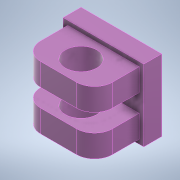
# Autodesk Inventor part: sliding_link
Saved by Autodesk Inventor 2022 (Build 260153000, 153)
## iProperties
Created: 2024-11-08
Part Number: sliding_link
Material: Generic
Document SubType Name: Modeling
Designer: Dell
Density: 1 g/cm^3
Appearance: Smooth - Purple
Author: Dell
Autodesk Inventor part; units mm, degrees
ref_plane "YZ Plane" through (0, 0, 0) normal (1, 0, 0) x (0, 1, 0)
ref_plane "XZ Plane" through (0, 0, 0) normal (0, 1, 0) x (-1, 0, 0)
ref_plane "XY Plane" through (0, 0, 0) normal (0, 0, 1) x (1, 0, 0)
sketch "Sketch1" plane through (0, 0, 0) normal (0, 0, 1) x (1, 0, 0)
  line L0 (0, 0) -> (-9, 0)
  line L1 (-9, 0) -> (-9, 8)
  line L2 (-9, 8) -> (0, 8)
  line L3 (0, 8) -> (0, 0)
  dimension "d0" = 9
  dimension "d1" = 8
  constraints: 8 end point, 2 parallel, 1 horizontal, 1 perpendicular
  measures "d0" distance of L1.end L2.end
  measures "d1" distance of L0.end L1.end
extrude "Extrusion1" add sketch "Sketch1" along normal blind 2
sketch "Sketch2" plane through (0, 0, 2) normal (0, 0, 1) x (1, 0, 0)
  line L0 (0, 0) -> (0, 8) projected
  line L1 (0, 8) -> (-9, 8) projected
  line L2 (-0.5, 0.5) -> (-8.5, 0.5)
  line L3 (-8.5, 0.5) -> (-8.5, 3)
  line L4 (-8.5, 3) -> (-0.5, 3)
  line L5 (-0.5, 3) -> (-0.5, 0.5)
  line L6 (-9, 0) -> (0, 0) projected
  line L7 (-0.5, 5) -> (-8.5, 5)
  line L8 (-8.5, 5) -> (-8.5, 7.5)
  line L9 (-8.5, 7.5) -> (-0.5, 7.5)
  line L10 (-0.5, 7.5) -> (-0.5, 5)
  dimension "d8" = 2.5
  dimension "d9" = 0.5
  dimension "d10" = 2.5
  dimension "d11" = 0.5
  constraints: 16 end point, 4 parallel, 2 horizontal, 2 perpendicular
  measures "d8" distance of L2.end L3.end
  measures "d9" distance between parallel lines of L6 L2
  measures "d10" distance of L7.end L8.end
  measures "d11" distance between parallel lines of L9 L1
extrude "Extrusion2" add sketch "Sketch2" along normal blind 5
sketch "Sketch3" plane through (-8.5, 0.5, 2) normal (0, -1, 0) x (1, 0, 0)
  circle A0 centre (4, 2.5) radius 1.75
  line L0 (8, 0) -> (8, 5) projected
  line L1 (0, 5) -> (8, 5) projected
  point P0 (8.5, -2)
  dimension "d14" = 3.5
  dimension "d15" = 4
  dimension "d16" = 2.5
  constraints: 1 centre point
  measures "d14" diameter of A0
  measures "d15" distance from line of L0 A0.centre
  measures "d16" distance from line of A0.centre L1
extrude "Extrusion3" cut sketch "Sketch3" against normal through all
fillet "Fillet1" radius 2 4 edges at (-8.5, 6.25, 7) (-8.5, 1.75, 7) (-0.5, 6.25, 7) (-0.5, 1.75, 7)
body "Solid1"
